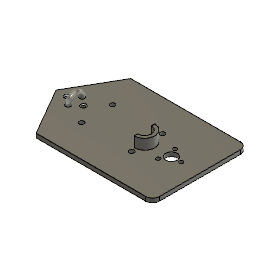
astra-base-template (Autodesk Fusion 360 design; units mm, degrees)
part number: 2026-06-18-14-17-35-325
Autodesk Fusion 360 part; units mm, degrees
sketch "Sketch1" plane through (0, 0, 0) normal (0, 1, 0) x (1, 0, 0)
  line L0 (45, 5) -> (-125, 5)
  line L1 (-125, -133.133) -> (45, -133.133)
  line L2 (45, -133.133) -> (45, 5)
  line L3 (45, -64.0665) -> (-260, -64.0665)
  line L4 (-125, -133.133) -> (-164.8756, -64.0665)
  line L5 (-125, -133.133) -> (-45.2489, -133.133) construction
  line L6 (-125, 5) -> (-164.8756, -64.0665)
  line L7 (45, -133.133) -> (-32, -133.133)
  line L8 (-32, -133.133) -> (-32, -86.566)
  circle A0 centre (-32, -86.566) radius 3.5
  line L9 (-32, -86.566) -> (-105, -86.566)
  circle A1 centre (-105, -86.566) radius 3.5
  line L10 (45, -64.0665) -> (3.387, -64.0665)
  circle A2 centre (3.387, -64.0665) radius 20
  circle A3 centre (3.387, -64.0665) radius 8.5
  line L11 (23.387, -64.0665) -> (3.387, -64.0665)
  line L12 (3.387, -64.0665) -> (-6.613, -46.746)
  line L13 (3.387, -64.0665) -> (-6.613, -81.387)
  line L14 (23.387, -64.0665) -> (17.387, -64.0665)
  circle A4 centre (17.387, -64.0665) radius 3
  line L15 (-6.613, -46.746) -> (-3.613, -51.9421)
  line L16 (-6.613, -81.387) -> (-3.613, -76.1909)
  circle A5 centre (-3.613, -51.9421) radius 3
  circle A6 centre (-3.613, -76.1909) radius 3
  circle A7 centre (-32, -41.567) radius 3.5
  circle A8 centre (-105, -41.567) radius 3.5
  line L17 (45, -64.0665) -> (-125, -64.0665)
  circle A9 centre (-125, -64.0665) radius 2.5
  line L18 (-125, -64.0665) -> (-149, -64.0665)
  circle A10 centre (-149, -64.0665) radius 2.5
  dimension "d1" = 170
  dimension "d2" = 138.133
  dimension "d3" = 120
  dimension "d4" = 77
  dimension "d5" = 46.567
  dimension "d6" = 7
  dimension "d7" = 73
  dimension "d8" = 7
  dimension "d9" = 41.613
  dimension "d10" = 40
  dimension "d11" = 17
  dimension "d12" = 120
  dimension "d13" = 20
  dimension "d15" = 20
  dimension "d16" = 6
  dimension "d17" = 6
  dimension "d18" = 6
  dimension "d19" = 6
  dimension "d20" = 6
  dimension "d21" = 6
  dimension "d22" = 170
  dimension "d23" = 5
  dimension "d24" = 24
  dimension "d25" = 5
  constraint horizontal L0
  constraint horizontal L1
  constraint vertical L2
  constraint midpoint L2 L3.start
  constraint horizontal L5
  constraint coincident L3 L4.end
  constraint perpendicular L2 L7
  constraint perpendicular L1 L8
  constraint coincident L8.end A0.centre
  constraint perpendicular L8 L9
  constraint coincident L9.end A1.centre
  constraint perpendicular L2 L10
  constraint coincident L10.end A2.centre
  constraint concentric A2 A3
  constraint coincident L10 L11.start
  constraint coincident A2 L11.start
  constraint parallel L3 L11
  constraint parallel L11 L14
  constraint coincident L14.end A4.centre
  constraint parallel L12 L15
  constraint parallel L13 L16
  constraint coincident L15.end A5.centre
  constraint coincident L16.end A6.centre
  constraint symmetric L3 A0 A7
  constraint symmetric L3 A1 A8
  constraint perpendicular L2 L17
  constraint coincident L17.end A9.centre
  constraint parallel L3 L18
  constraint coincident L18.end A10.centre
  measures "d1" distance of L0.start L0.end
  measures "d2" distance of L0.start L1.end
  measures "d3" angle of L4 L5
  measures "d4" distance of L1.end L7.end
  measures "d5" distance of L7.end L8.end
  measures "d6" diameter of A0
  measures "d7" distance of L8.end L9.end
  measures "d8" diameter of A1
  measures "d9" distance of L3.start L10.end
  measures "d10" diameter of A2
  measures "d11" diameter of A3
  measures "d12" angle of L11 L12
  measures "d13" distance of L10.end L12.end
  measures "d15" distance of L10.end L13.end
  measures "d16" distance of L11.start L14.end
  measures "d17" diameter of A4
  measures "d18" distance of L12.end L15.end
  measures "d19" distance of L13.end L16.end
  measures "d20" diameter of A5
  measures "d21" diameter of A6
  measures "d22" distance of L3.start L17.end
  measures "d23" diameter of A9
  measures "d24" distance of L17.end L18.end
  measures "d25" diameter of A10
extrude "Extrude1" add sketch "Sketch1" along normal blind 6 contours L0 L2 L3 L6 L10 A2 L17 A9 L18 A10 | L1 L2 L3 L4 L7 L10 A2 L17 A9 L18 A10 | L3 L10 A2 A3 L11 L13 L14 A4 L16 A6 L17 | L3 L10 A2 A3 L11 L12 L14 A4 L15 A5 L17 | L3 A2 A3 L12 L15 A5 L17 | L3 A2 A3 L13 L16 A6 L17
sketch "Sketch2" plane through (0, 6, 0) normal (0, 1, 0) x (-1, 0, 0)
  circle A0 centre (105, 41.567) radius 3.5
  line L0 (-45, -5) -> (125, -5)
  line L1 (125, -5) -> (164.8756, 64.0665)
  line L2 (164.8756, 64.0665) -> (125, 133.133)
  line L3 (125, 133.133) -> (-45, 133.133)
  line L4 (-45, 133.133) -> (-45, -5)
  circle A1 centre (125, 64.0665) radius 2.5
  circle A2 centre (105, 86.566) radius 3.5
  circle A3 centre (3.613, 76.1909) radius 3
  circle A4 centre (-3.387, 64.0665) radius 8.5
  circle A5 centre (3.613, 51.9421) radius 3
  circle A6 centre (32, 86.566) radius 3.5
  circle A7 centre (-17.387, 64.0665) radius 3
  circle A8 centre (32, 41.567) radius 3.5
  circle A9 centre (149, 64.0665) radius 2.5
  line L5 (125, 64.0665) -> (149, 64.0665)
  line L6 (137, 64.0665) -> (137, 54.0665)
  circle A10 centre (137, 54.0665) radius 3.75
  line L7 (-45, 65) -> (35, 65)
  circle A11 centre (35, 65) radius 10
  circle A12 centre (35, 65) radius 15
  line L8 (35, 50) -> (35, 80)
  dimension "d28" = 10
  dimension "d29" = 7.5
  dimension "d31" = 80
  dimension "d32" = 20
  dimension "d33" = 30
  constraint coincident A1.centre L5.start
  constraint coincident A9.centre L5.end
  constraint midpoint L5 L6.start
  constraint perpendicular L5 L6
  constraint coincident L6.end A10.centre
  constraint coincident L4 L7.start
  constraint perpendicular L4 L7
  constraint coincident L7.end A11.centre
  constraint concentric A11 A12
  constraint coincident A12 L8.start
  constraint coincident A12 L8.end
  constraint vertical L8
  measures "d28" distance of L6.start L6.end
  measures "d29" diameter of A10
  measures "d31" distance of L7.start L7.end
  measures "d32" diameter of A11
  measures "d33" diameter of A12
revolve "Revolve1" add sketch "Sketch2" angle 180 about axis through (-125, 6, 64.0665) along (1, 0, 0) contours A10
extrude "Extrude2" add sketch "Sketch2" along normal blind 15 contours L7 A11 A12 L8 | L7 A11 A12 L8
chamfer "Chamfer3" distance 1.5 angle 45 1 edges at (-151.3308, 6, 63.1625) tangent chain off
chamfer "Chamfer4" distance 1.5 angle 45 1 edges at (-127.3308, 6, 63.1625) tangent chain off
fillet "Fillet1" radius 10 1 edges at (45, 3, 133.133)
fillet "Fillet2" radius 10 1 edges at (45, 3, -5)
sketch "Sketch3" plane through (0, 0, 0) normal (1, 0, 0) x (0, 1, 0)
named bodies: "astra-base-template"
